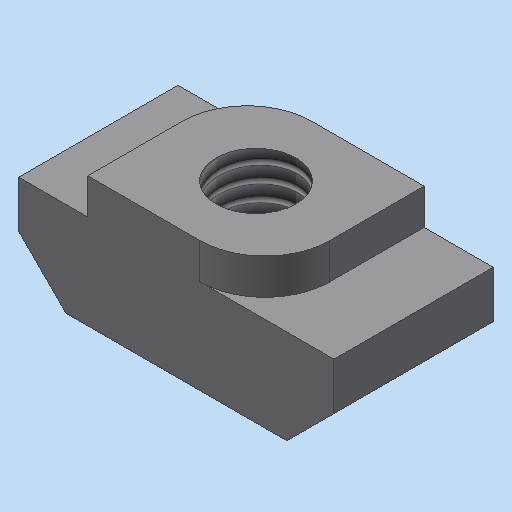
# Autodesk Inventor part: 3842530285_050629_001
Saved by Autodesk Inventor 2023.3 (Build 273359000, 359)
## iProperties
Shininess: 64.0
Length Units: 11269
Angle Units: 11279
Time Units: 11290
Mass Units: 11283
Length Display Precision: 3
Angle Display Precision: 2
Compacted: True
Part Number: 3842530285_050629_001
Document SubType Name: Modeling
Created: 2005-06-29
Material: Allgemein
Manufacturer: Standard
Standards Organization: Custom
Description: =<RBPARTNOTITLE2>
Vendor: Bosch Rexroth
Density: 1 g/cm^3
Appearance: Vorgabe
Mass: 1.08827 g
Surface Area: 8.37971 cm^2
Volume: 1.08827 cm^3
GAIN_REFID: 20__3842530285_050629_001:420D8
Control State: 0
Master: False
Checked Out: False
RBPARTNOTITLE2: Hammermutter M6/Nut10
RBPARTMADEOF: 3842530285
RBDRAWINGMISSINGSPEC: --
AnP_Kategorie: 2
Density: 0.0
Volumn: 0.0
Area: 0.0
PropertySet Name: Model Information
Keywords: =<RBPARTMADEOF>
Comments: =<RBSURFACE2>
Revision Number: 01
Autodesk Inventor part; units mm, degrees
ref_plane "YZ Plane" through (0, 0, 0) normal (1, 0, 0) x (0, 1, 0)
ref_plane "XZ Plane" through (0, 0, 0) normal (0, 1, 0) x (-1, 0, 0)
ref_plane "XY Plane" through (0, 0, 0) normal (0, 0, 1) x (1, 0, 0)
sketch "Skizze1" plane through (0, 0, 0) normal (0, 0, 1) x (1, 0, 0)
  line L0 (0.6, 0) -> (20, 0)
  line L1 (20, 0) -> (20, 9.8)
  line L2 (20, 9.8) -> (0.6, 9.8)
  line L3 (0.6, 9.8) -> (0.6, 0)
  dimension "d2" = 9.8
  dimension "d3" = 19.4
  constraints: 8 end point, 2 parallel, 1 horizontal, 1 perpendicular
  measures "d2" distance of L1.end L0.end
  measures "d3" distance of L0.end L0.start
extrude "Extrusion1" add sketch "Skizze1" along normal blind 8
sketch "Skizze2" plane through (0.6, 0, 0) normal (0, -1, 0) x (1, 0, 0)
  line L0 (0, 8) -> (4.25, 8)
  line L1 (4.25, 8) -> (4.25, 5.8)
  line L2 (4.25, 5.8) -> (0, 5.8)
  line L3 (0, 5.8) -> (0, 8)
  line L4 (19.4, 8) -> (15.15, 8)
  line L5 (15.15, 8) -> (15.15, 5.8)
  line L6 (15.15, 5.8) -> (19.4, 5.8)
  line L7 (19.4, 5.8) -> (19.4, 8)
  dimension "d13" = 4.25
  dimension "d14" = 2.2
  dimension "d15" = 2.2
  dimension "d16" = 4.25
  constraints: 16 end point, 4 parallel, 2 horizontal, 2 perpendicular
  measures "d13" distance of L1.end L2.end
  measures "d14" distance of L0.end L1.end
  measures "d15" distance of L4.end L5.end
  measures "d16" distance of L5.end L6.end
extrude "Extrusion2" cut sketch "Skizze2" against normal through all
sketch "Skizze3" plane through (0.6, 0, 0) normal (0, -1, 0) x (1, 0, 0)
  line L0 (0, 0) -> (0, 5.8) projected
  line L1 (0, 0) -> (19.4, 0) projected
  line L2 (19.4, 0) -> (19.4, 5.8) projected
  line L3 (0, 0) -> (0, 2.9)
  line L4 (0, 2.9) -> (2.9, 0)
  line L5 (0, 0) -> (2.9, 0)
  line L6 (19.4, 0) -> (19.4, 2.9)
  line L7 (19.4, 2.9) -> (16.5, 0)
  line L8 (16.5, 0) -> (19.4, 0)
  dimension "d19" = 45
  constraints: 12 end point, 2 midpoint, 1 collinear, 1 perpendicular, 1 point on line
  measures "d19" angle of L5 L4
extrude "Extrusion3" cut sketch "Skizze3" against normal through all
sketch "Skizze8" plane through (0, 0, 8) normal (0, 0, 1) x (1, 0, 0)
  line L0 (4.85, 0) -> (15.75, 9.8)
  point P0 (10.3, 4.9)
  constraints: 2 end point, 1 midpoint
hole "Bohrung2" at (10.3, 4.9, 8) direction (0, 0, -1) diameter 4.917 end through all thread size "M6x1" class "6H" standard "ISO Metrisches Profil"
fillet "Rundung3" radius 4 1 edges at (15.75, 0, 6.9)
fillet "Rundung4" radius 4 1 edges at (4.85, 9.8, 6.9)
